Untitled (RnS56UNs) (Autodesk Fusion 360 design; units mm, degrees)
Autodesk Fusion 360 part; units mm, degrees
sketch "Sketch1" plane through (0, 0, 0) normal (0, 1, 0) x (1, 0, 0)
  circle A0 centre (0, 0) radius 20
  line L0 (0, 0) -> (20, 0)
  line L1 (0, 0) -> (-20, 0)
  dimension "d1" = 40
  constraint coincident A0.centre L0.start
  constraint coincident A0 L0.end
  constraint horizontal L0
  constraint coincident A0 L1.end
  constraint parallel L0 L1
  measures "d1" diameter of A0
extrude "Extrude1" add sketch "Sketch1" along normal blind 30 contours A0 L0 L1 picked at (-13.2589, 0.9936) makes body 1
sketch "Sketch2" plane through (0, 0, 0) normal (0, 0, 1) x (1, 0, 0)
  line L0 (-20, 0) -> (20, 0)
  line L1 (20, 0) -> (20, 30)
  line L2 (20, 30) -> (-20, 30)
  line L3 (-20, 30) -> (-20, 0)
  line L4 (20, 0) -> (20, 15)
  line L5 (25, 12.5) -> (15, 12.5)
  line L6 (15, 12.5) -> (15, 17.5)
  line L7 (15, 17.5) -> (25, 17.5)
  line L8 (25, 17.5) -> (25, 12.5)
  line L9 (25, 12.5) -> (15, 17.5) construction
  line L10 (15, 12.5) -> (25, 17.5) construction
  point P0 (20, 15)
  dimension "d4" = 10
  dimension "d5" = 5
  constraint coincident L0.end L1.start
  constraint midpoint L1 P0
  constraint perpendicular L5 L6
  constraint parallel L5 L7
  constraint parallel L6 L8
  constraint horizontal L5
  constraint coincident L9 P0
  constraint coincident L10 P0
  constraint coincident P0 L4.end
  measures "d4" distance of L6.end L7.end
  measures "d5" distance of L5.end L6.end
extrude "Extrude2" add sketch "Sketch2" along normal blind 2.5 and the other way blind 2.5 separate body contours L1 L4 L5 L7 L8 makes body 2
sketch "Sketch3" plane through (20, 0, 0) normal (-1, 0, 0) x (0, 0, 1)
  line L0 (-2.5, 12.5) -> (2.5, 12.5)
  line L1 (2.5, 12.5) -> (2.5, 17.5)
  line L2 (2.5, 17.5) -> (-2.5, 17.5)
  line L3 (-2.5, 17.5) -> (-2.5, 12.5)
  line L4 (0, 17.5) -> (0, 12.5)
  constraint midpoint L2 L4.start
  constraint midpoint L0 L4.end
extrude "Extrude3" add sketch "Sketch3" along normal blind 2 contours L0 L2 L3 L4 bodies 2
combine "Combine1" operation add target body 2 tool bodies 1
fillet "Fillet1" radius 2.5 3 edges at (25, 15, -2.5) (25, 15, 2.5) (20, 15, 2.5) on bodies 2
sketch "Sketch4" plane through (0, 17.5, 0) normal (0, 1, 0) x (-1, 0, 0)
  arc A0 (-20, 0) -> (-22.5, -2.5) centre (-22.5, 0) ccw
  line L0 (-22.5, -2.5) -> (-19.8431, -2.5)
  arc A1 (-20, 0) -> (-19.8431, -2.5) centre (0, 0) ccw
  circle A2 centre (-22.5, 0) radius 1
  dimension "d13" = 2
  constraint concentric A0 A2
  measures "d13" diameter of A2
extrude "Extrude4" cut sketch "Sketch4" against normal blind 5 contours A2 bodies 2
fillet "Fillet2" radius 0.5 2 edges at (23.4323, 17.5, 0.3616) (23.4323, 12.5, -0.3616) on bodies 2
sketch "Sketch5" plane through (0, 0, 0) normal (0, -1, 0) x (1, 0, 0)
  arc A0 (-20, 0) -> (20, 0) centre (0, 0) ccw
  line L0 (20, 0) -> (-20, 0)
  line L1 (0, -20) -> (0, -25)
  line L2 (0, -25) -> (-2.5, -25)
  line L3 (0, -25) -> (2.5, -25)
  line L4 (2.5, -25) -> (0.0913, -25.6696)
  line L5 (-2.5, -25) -> (-2.5, -19.8431)
  line L6 (2.5, -25) -> (2.5, -19.8431)
  dimension "d17" = 5
  dimension "d18" = 2.5
  constraint midpoint A0 L1.start
  constraint vertical L1
  constraint perpendicular L1 L2
  constraint perpendicular L1 L3
  constraint coincident A0 L5.end
  constraint vertical L5
  constraint coincident A0 L6.end
  constraint vertical L6
  measures "d17" distance of L1.start L1.end
  measures "d18" distance of L1.end L2.end
extrude "Extrude5" add sketch "Sketch5" along normal blind 2.5 and the other way blind 2.5 contours A0 L1 L2 L5 | A0 L1 L3 L6 bodies 2
fillet "Fillet3" radius 2.5 3 edges at (0, -2.5, -20) (0, -2.5, -25) (0, 2.5, -25) on bodies 2
sketch "Sketch6" plane through (-2.5, 0, 0) normal (-1, 0, 0) x (0, 0, 1)
  arc A0 (-22.5, 2.5) -> (-22.5, -2.5) centre (-22.5, 0) ccw
  line L0 (-22.5, -2.5) -> (-22.3607, -2.5)
  spline S0 degree 3 poles (-19.8431, 0) (-19.8431, -0.3078) (-19.9156, -0.67) (-20.1526, -1.2395) (-20.3595, -1.5473) (-20.7985, -1.9843) (-21.1086, -2.1904) (-21.6832, -2.4275) (-22.0495, -2.5) (-22.3607, -2.5) knots 0.742812 0.742812 0.742812 0.742812 0.835155 0.835155 0.927869 0.927869 1.020976 1.020976 1.114329 1.114329 1.114329 1.114329
  line L1 (-19.8431, 0) -> (-19.8431, 2.5)
  line L2 (-19.8431, 2.5) -> (-22.5, 2.5)
  circle A1 centre (-22.5, 0) radius 1
  dimension "d24" = 2
  constraint concentric A0 A1
  measures "d24" diameter of A1
extrude "Extrude6" cut sketch "Sketch6" against normal blind 5 contours A1 bodies 2
fillet "Fillet4" radius 0.5 2 edges at (2.5, -0.3616, -23.4323) (-2.5, 0.3616, -23.4323) on bodies 2
sketch "Sketch7" plane through (0, 0, 0) normal (0, -1, 0) x (1, 0, 0)
  arc A0 (2.5, -19.8431) -> (20, 0) centre (0, 0) ccw
  line L0 (20, 0) -> (-20, 0)
  arc A1 (-20, 0) -> (-2.5, -19.8431) centre (0, 0) ccw
  arc A2 (-2.5, -19.8431) -> (2.5, -19.8431) centre (0, 0) ccw
